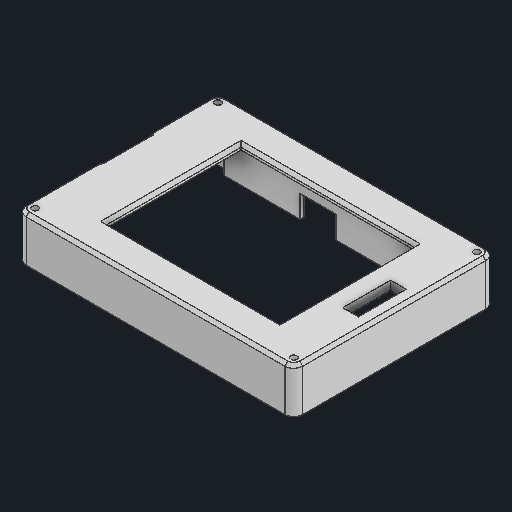
# Autodesk Inventor part: m1case
Saved by Autodesk Inventor 2027 (Build 310192000, 192)
## iProperties
Created: 2026-10-08
Part Number: m1case
Material: 일반
Document SubType Name: Modeling
Designer: khw
Density: 1 g/cm^3
Appearance: 기본값
Author: khw
Autodesk Inventor part; units mm, degrees
ref_plane "YZ Plane" through (0, 0, 0) normal (1, 0, 0) x (0, 1, 0)
ref_plane "XZ Plane" through (0, 0, 0) normal (0, 1, 0) x (-1, 0, 0)
ref_plane "XY Plane" through (0, 0, 0) normal (0, 0, 1) x (1, 0, 0)
sketch "스케치1" plane through (0, 0, 0) normal (0, 1, 0) x (-1, 0, 0)
  line L0 (-35, 25.5) -> (35, 25.5)
  line L1 (35, 25.5) -> (35, -25.5)
  line L2 (35, -25.5) -> (-35, -25.5)
  line L3 (-35, -25.5) -> (-35, 25.5)
  line L4 (-35, 25.5) -> (35, -25.5) construction
  line L5 (35, 25.5) -> (-35, -25.5) construction
  line L6 (-39.25, 21) -> (39.25, 21) construction
  line L7 (39.25, 21) -> (39.25, -21) construction
  line L8 (39.25, -21) -> (-39.25, -21) construction
  line L9 (-39.25, -21) -> (-39.25, 21) construction
  line L10 (-39.25, 21) -> (39.25, -21) construction
  line L11 (39.25, 21) -> (-39.25, -21) construction
  circle A0 centre (39.25, 21) radius 1.1
  circle A1 centre (39.25, -21) radius 1.1
  circle A2 centre (-39.25, -21) radius 1.1
  circle A3 centre (-39.25, 21) radius 1.1
  line L12 (-44.25, 27.5) -> (44.25, 27.5)
  line L13 (44.25, 27.5) -> (44.25, -27.5)
  line L14 (44.25, -27.5) -> (-44.25, -27.5)
  line L15 (-44.25, -27.5) -> (-44.25, 27.5)
  line L16 (-44.25, 27.5) -> (44.25, -27.5) construction
  line L17 (44.25, 27.5) -> (-44.25, -27.5) construction
  line L18 (-46.25, -29.5) -> (46.25, -29.5)
  line L19 (46.25, -29.5) -> (46.25, 29.5)
  line L20 (46.25, 29.5) -> (-46.25, 29.5)
  line L21 (-46.25, 29.5) -> (-46.25, -29.5)
  circle A4 centre (-39.25, 21) radius 3
  circle A5 centre (-39.25, -21) radius 3
  circle A6 centre (39.25, -21) radius 3
  circle A7 centre (39.25, 21) radius 3
  line L22 (-36.25, 21) -> (-36.25, 27.5)
  line L23 (-39.25, 18) -> (-44.25, 18)
  line L24 (-39.25, -18) -> (-44.25, -18)
  line L25 (-36.25, -21) -> (-36.25, -27.5)
  line L26 (39.25, -18) -> (44.25, -18)
  line L27 (36.25, -21) -> (36.25, -27.5)
  line L28 (39.25, 18) -> (44.25, 18)
  line L29 (36.25, 21) -> (36.25, 27.5)
  point P0 (0, 0)
  dimension "d0" = 70
  dimension "d1" = 51
  dimension "d2" = 78.5
  dimension "d3" = 42
  dimension "d4" = 2.2
  dimension "d5" = 2.2
  dimension "d6" = 2.2
  dimension "d7" = 2.2
  dimension "d8" = 2
  dimension "d9" = 5
  dimension "d10" = 2
  dimension "d16" = 6
  dimension "d17" = 6
  dimension "d18" = 6
  dimension "d19" = 6
  constraints: 60 end point, 18 point on line, 10 perpendicular, 8 centre point, 8 coincident, 8 parallel, 8 point on circle, 6 midpoint, 5 tangent, 3 horizontal, 3 other
  measures "d0" distance of L1.end L2.end
  measures "d1" distance of L0.end L1.end
  measures "d2" distance of L7.end L8.end
  measures "d3" distance of L6.end L7.end
  measures "d4" diameter of A0
  measures "d5" diameter of A1
  measures "d6" diameter of A2
  measures "d7" diameter of A3
  measures "d8" distance between parallel lines of L14 L2
  measures "d9" distance from line of L13 L7.end
  measures "d10" distance between parallel lines of L14 L18
  measures "d16" diameter of A5
  measures "d17" diameter of A4
  measures "d18" diameter of A6
  measures "d19" diameter of A7
extrude "돌출1" add sketch "스케치1" along normal blind 3 contours A0 | A1 | A2 | A3 | L12 L22 A4 L23 L15 | L12 L29 A7 L28 L13 L26 A6 L27 L14 L25 A5 L24 L15 L23 A4 L22 | L12 L13 L28 A7 L29 | A4 | L24 A5 L25 L14 L15 | A7 | A5 | L13 L14 L27 A6 L26 | A6 | L21 L20 L19 L18
extrude "돌출2" add sketch "스케치1" against normal blind 10 contours L21 L20 L19 L18
extrude "돌출3" add sketch "스케치1" against normal blind 3 contours L12 L22 A4 L23 L15 | L12 L13 L28 A7 L29 | A4 | L24 A5 L25 L14 L15 | A7 | A5 | L13 L14 L27 A6 L26 | A6
ref_plane "작업 평면1" through (0, 1.2, 0) normal (0, -1, 0) x (1, 0, 0)
sketch "스케치3" plane through (0, 1.2, 0) normal (0, -1, 0) x (1, 0, 0)
  line L0 (-39.25, 18) -> (-44.25, 18) projected
  line L1 (-44.25, 18) -> (-44.25, -18) projected
  line L2 (-44.25, -18) -> (-39.25, -18) projected
  arc A0 (-36.25, -21) -> (-39.25, -18) centre (-39.25, -21) ccw projected
  line L3 (-36.25, -21) -> (-36.25, -27.5) projected
  line L4 (-36.25, -27.5) -> (36.25, -27.5) projected
  line L5 (36.25, -27.5) -> (36.25, -21) projected
  arc A1 (39.25, -18) -> (36.25, -21) centre (39.25, -21) ccw projected
  line L6 (39.25, -18) -> (44.25, -18) projected
  line L7 (44.25, -18) -> (44.25, 18) projected
  line L8 (44.25, 18) -> (39.25, 18) projected
  arc A2 (36.25, 21) -> (39.25, 18) centre (39.25, 21) ccw projected
  line L9 (36.25, 21) -> (36.25, 27.5) projected
  line L10 (36.25, 27.5) -> (-36.25, 27.5) projected
  line L11 (-36.25, 27.5) -> (-36.25, 21) projected
  arc A3 (-39.25, 18) -> (-36.25, 21) centre (-39.25, 21) ccw projected
  line L12 (35, 25.5) -> (-35, 25.5) projected
  line L13 (35, -25.5) -> (35, 25.5) projected
  line L14 (-35, -25.5) -> (35, -25.5) projected
  line L15 (-35, 25.5) -> (-35, -25.5) projected
  line L16 (30.5, 22.5) -> (-27.5, 22.5)
  line L17 (-27.5, 22.5) -> (-27.5, -22.5)
  line L18 (-27.5, -22.5) -> (30.5, -22.5)
  line L19 (30.5, -22.5) -> (30.5, 22.5)
  line L20 (35, -25.5) -> (35, 25.5) projected
  point P0 (0, 0)
  point P1 (-27.5, 0)
  point P2 (30.5, 0)
  point P3 (35, 0)
  dimension "d23" = 58
  dimension "d24" = 45
  dimension "d25" = 7.5
  constraints: 8 end point, 3 midpoint, 2 parallel, 1 horizontal, 1 horizontal alignment, 1 perpendicular
  measures "d23" distance of L18.end L17.end
  measures "d24" distance of L17.end L16.end
  measures "d25" distance from line of L15 point (-27.5, 0)
extrude "돌출4" add sketch "스케치3" against normal up to surface (1.8 mm away) contours L13 L14 L15 L12
chamfer "모따기1" distance 1 angle 45 4 edges at (1.5, 3, -22.5) (-27.5, 3, 0) (1.5, 3, 22.5) (30.5, 3, 0)
ref_plane "작업 평면2" through (0, -4.5, 0) normal (0, -1, 0) x (1, 0, 0)
sketch "스케치4" plane through (0, -4.5, 0) normal (0, -1, 0) x (1, 0, 0)
  line L0 (-46.25, -6.5) -> (-44.25, -6.5)
  line L1 (-44.25, -6.5) -> (-44.25, 2.5)
  line L2 (-44.25, 2.5) -> (-46.25, 2.5)
  line L3 (-46.25, 2.5) -> (-46.25, -6.5)
  line L4 (-44.25, -27.5) -> (-44.25, 27.5) projected
  line L5 (-46.25, 29.5) -> (-46.25, -29.5) projected
  line L6 (-45.25, -10.5) -> (-46.25, -10.5)
  line L7 (-46.25, -10.5) -> (-46.25, 6.5)
  line L8 (-46.25, 6.5) -> (-45.25, 6.5)
  line L9 (-45.25, 6.5) -> (-45.25, -10.5)
  point P0 (0, 0)
  point P1 (-45.25, -6.5)
  point P2 (-45.25, 2.5)
  point P3 (-46.25, 6.5)
  point P4 (-46.25, -10.5)
  point P5 (-44.25, 0)
  point P6 (-44.25, -2)
  point P7 (-46.25, -2)
  dimension "d32" = 9
  dimension "d33" = 1
  dimension "d34" = 4
  dimension "d86" = 2
  constraints: 16 end point, 4 midpoint, 4 parallel, 2 horizontal, 2 perpendicular, 2 point on line
  measures "d32" distance of L1.end L0.end
  measures "d33" distance between parallel lines of L3 L9
  measures "d34" distance between parallel lines of L0 L6
  measures "d86" distance of point (-44.25, 0) point (-44.25, -2)
extrude "돌출5" cut sketch "스케치4" along normal blind 10
sketch "스케치5" plane through (0, 0, 0) normal (0, -1, 0) x (1, 0, 0)
  line L0 (37, 8) -> (42.25, 8)
  line L1 (42.25, 8) -> (42.25, -8)
  line L2 (42.25, -8) -> (37, -8)
  line L3 (37, -8) -> (37, 8)
  line L4 (44.25, 27.5) -> (44.25, -27.5) projected
  line L5 (35, -25.5) -> (35, 25.5) projected
  line L6 (37, 8) -> (42.25, 7.1992)
  line L7 (37, 5.9769) -> (39.9421, 5.5281)
  line L8 (39.9421, 5.5281) -> (38.5, 4)
  line L9 (38.5, 4) -> (42.25, 4) construction
  line L10 (42.25, 5.0596) -> (41.25, 4)
  line L11 (37, 0) -> (42.25, 0.8008)
  line L12 (37, 2.0231) -> (39.9421, 2.4719)
  line L13 (39.9421, 2.4719) -> (38.5, 4)
  line L14 (42.25, 2.9404) -> (41.25, 4)
  line L15 (42.25, -3) -> (41.75, -2.5)
  line L16 (41.75, -2.5) -> (40.75, -2.5)
  line L17 (40.75, -2.5) -> (40.75, -3)
  line L18 (40.75, -3) -> (37.5, -3)
  line L19 (37.5, -3) -> (37, -2.5)
  line L20 (37, -5.5) -> (37.5, -5)
  line L21 (37.5, -5) -> (42.25, -5)
  line L22 (37.5, -3) -> (37.5, -5) construction
  point P0 (0, 0)
  point P1 (42.25, 0)
  point P2 (44.25, 0)
  point P3 (39.221, 4.764)
  point P4 (39.221, 3.236)
  point P5 (39.875, -5)
  point P6 (37.5, -4)
  dimension "d37" = 2
  dimension "d38" = 2
  dimension "d39" = 16
  dimension "d40" = 2
  dimension "d41" = 2
  dimension "d42" = 2
  dimension "d43" = 1
  dimension "d44" = 0.5
  dimension "d45" = 4
  dimension "d46" = 0.5
  dimension "d47" = 45
  dimension "d48" = 1.5
  dimension "d49" = 1
  dimension "d50" = 1.5
  dimension "d51" = 8.673
  constraints: 42 end point, 10 point on line, 6 midpoint, 6 symmetric about line, 5 parallel, 5 perpendicular, 2 horizontal, 1 horizontal alignment, 1 vertical
  measures "d37" distance between parallel lines of L4 L1
  measures "d38" distance between parallel lines of L3 L5
  measures "d39" distance of L0.end L1.end
  measures "d40" distance between parallel lines of L7 L6
  measures "d41" distance from line of L10 point (39.221, 4.764)
  measures "d42" distance from line of point (39.875, -5) L18
  measures "d43" distance of L15.end L16.end
  measures "d44" distance of L16.end L17.end
  measures "d45" vertical distance of L11.start point (37.5, -4)
  measures "d46" distance between parallel lines of L3 L22
  measures "d47" angle of L17 L15
  measures "d48" distance of L15.start L17.end
  measures "d49" distance of L9.end L10.end
  measures "d50" distance from line of L3 L8.end
  measures "d51" angle of L0 L6
extrude "돌출6" cut sketch "스케치5" against normal blind 10
sketch "스케치7" plane through (0, -10, 0) normal (0, -1, 0) x (1, 0, 0)
  line L0 (-45.25, -10.5) -> (-46.25, -10.5) projected
  line L1 (-46.25, -10.5) -> (-46.25, -29.5) projected
  line L2 (-46.25, -29.5) -> (46.25, -29.5) projected
  line L3 (46.25, -29.5) -> (46.25, 29.5) projected
  line L4 (46.25, 29.5) -> (-46.25, 29.5) projected
  line L5 (-46.25, 29.5) -> (-46.25, 6.5) projected
  line L6 (-46.25, 6.5) -> (-45.25, 6.5) projected
  line L7 (-45.25, 6.5) -> (-45.25, 2.5) projected
  line L8 (-45.25, 2.5) -> (-44.25, 2.5) projected
  line L9 (-44.25, 2.5) -> (-44.25, 27.5) projected
  line L10 (-44.25, 27.5) -> (44.25, 27.5) projected
  line L11 (44.25, 27.5) -> (44.25, -27.5) projected
  line L12 (44.25, -27.5) -> (-44.25, -27.5) projected
  line L13 (-44.25, -27.5) -> (-44.25, -6.5) projected
  line L14 (-44.25, -6.5) -> (-45.25, -6.5) projected
  line L15 (-45.25, -6.5) -> (-45.25, -10.5) projected
  line L16 (-46.25, 33.6) -> (46.25, 33.6)
  line L17 (46.25, 33.6) -> (46.25, -33.6)
  line L18 (46.25, -33.6) -> (-46.25, -33.6)
  line L19 (-46.25, -33.6) -> (-46.25, 33.6)
  line L20 (-46.25, -10.5) -> (-46.25, 6.5) projected
  line L21 (43.25, 30.6) -> (-43.25, 30.6) construction
  line L22 (-43.25, 30.6) -> (-43.25, -30.6) construction
  line L23 (-43.25, -30.6) -> (43.25, -30.6) construction
  line L24 (43.25, -30.6) -> (43.25, 30.6) construction
  circle A0 centre (-43.25, 30.6) radius 1.1
  circle A1 centre (43.25, 30.6) radius 1.1
  circle A2 centre (-43.25, -30.6) radius 1.1
  circle A3 centre (43.25, -30.6) radius 1.1
  line L25 (-46.25, -29.5) -> (46.25, -29.5) projected
  point P0 (0, 0)
  point P1 (46.25, 0)
  point P2 (-46.25, 0)
  point P3 (43.25, -29.5)
  point P4 (-43.25, -29.5)
  point P5 (-43.25, 29.5)
  point P6 (43.25, 29.5)
  dimension "d61" = 3
  dimension "d62" = 2.2
  dimension "d63" = 2.2
  dimension "d64" = 2.2
  dimension "d65" = 2.2
  constraints: 16 end point, 4 centre point, 4 coincident, 4 parallel, 3 midpoint, 2 perpendicular, 1 horizontal, 1 point on line, 1 tangent, 3 other
  measures "d61" distance between parallel lines of L16 L21
  measures "d62" diameter of A0
  measures "d63" diameter of A1
  measures "d64" diameter of A2
  measures "d65" diameter of A3
extrude "돌출8" add sketch "스케치7" against normal up to surface (13 mm away) contours L2 L17 L18 L19 | L19 L16 L17 L4
sketch "스케치6" plane through (0, -4.5, 0) normal (0, -1, 0) x (1, 0, 0)
  line L0 (-10.75, -29.5) -> (1.25, -29.5)
  line L1 (1.25, -29.5) -> (1.25, -27.5)
  line L2 (1.25, -27.5) -> (-10.75, -27.5)
  line L3 (-10.75, -27.5) -> (-10.75, -29.5)
  arc A0 (-36.25, -21) -> (-39.25, -18) centre (-39.25, -21) ccw projected
  line L4 (-39.25, -18) -> (-44.25, -18) projected
  line L5 (-44.25, -27.5) -> (-44.25, -18) projected
  line L6 (-36.25, -27.5) -> (-44.25, -27.5) projected
  line L7 (-36.25, -27.5) -> (-36.25, -21) projected
  circle A1 centre (-39.25, -21) radius 1.1 projected
  line L8 (44.25, -27.5) -> (-44.25, -27.5) projected
  line L9 (-46.25, -29.5) -> (46.25, -29.5) projected
  line L10 (1.25, -29.5) -> (5.35, -33.6)
  line L11 (-46.25, -33.6) -> (46.25, -33.6) projected
  line L12 (-10.75, -29.5) -> (-14.85, -33.6)
  point P0 (0, 0)
  point P1 (-4.75, -27.5)
  point P2 (-4.75, -29.5)
  dimension "d54" = 28.5
  dimension "d55" = 12
  dimension "d68" = 45
  dimension "d69" = 45
  constraints: 12 end point, 4 point on line, 2 midpoint, 2 parallel, 1 horizontal, 1 perpendicular
  measures "d54" distance from line of L3 A0.centre
  measures "d55" distance of L1.end L2.end
  measures "d68" angle of L9 L10
  measures "d69" angle of L9 L12
extrude "돌출7" cut sketch "스케치6" along normal blind 2 contours L3 L2 L1 L0 | L0 L10 L11 L12
fillet "모깎기1" radius 3 4 edges at (46.25, -3.5, 33.6) (46.25, -3.5, -33.6) (-46.25, -3.5, -33.6) (-46.25, -3.5, 33.6)
sketch "스케치8" plane through (0, 0, 0) normal (0, -1, 0) x (1, 0, 0)
  line L0 (37, 8) -> (42.25, 8) projected
  line L1 (42.25, 8) -> (42.25, -8) projected
  line L2 (42.25, -8) -> (37, -8) projected
  line L3 (37, -8) -> (37, 8) projected
  line L4 (-39.25, 18) -> (-44.25, 18) projected
  line L5 (-44.25, 18) -> (-44.25, -18) projected
  line L6 (-44.25, -18) -> (-39.25, -18) projected
  arc A0 (-36.25, -21) -> (-39.25, -18) centre (-39.25, -21) ccw projected
  line L7 (-36.25, -21) -> (-36.25, -27.5) projected
  line L8 (-36.25, -27.5) -> (36.25, -27.5) projected
  line L9 (36.25, -27.5) -> (36.25, -21) projected
  arc A1 (39.25, -18) -> (36.25, -21) centre (39.25, -21) ccw projected
  line L10 (39.25, -18) -> (44.25, -18) projected
  line L11 (44.25, -18) -> (44.25, 18) projected
  line L12 (44.25, 18) -> (39.25, 18) projected
  arc A2 (36.25, 21) -> (39.25, 18) centre (39.25, 21) ccw projected
  line L13 (36.25, 21) -> (36.25, 27.5) projected
  line L14 (36.25, 27.5) -> (-36.25, 27.5) projected
  line L15 (-36.25, 27.5) -> (-36.25, 21) projected
  arc A3 (-39.25, 18) -> (-36.25, 21) centre (-39.25, 21) ccw projected
  line L16 (35, 25.5) -> (-35, 25.5) projected
  line L17 (35, -25.5) -> (35, 25.5) projected
  line L18 (-35, -25.5) -> (35, -25.5) projected
  line L19 (-35, 25.5) -> (-35, -25.5) projected
  line L20 (36.25, -25.5) -> (-36.25, -25.5)
  line L21 (-10.75, -27.5) -> (1.25, -27.5) projected
  line L22 (1.25, -27.5) -> (1.25, -25.5)
  line L23 (-10.75, -25.5) -> (-10.75, -27.5)
  point P0 (0, 0)
  dimension "d74" = 2
  constraints: 6 end point, 4 point on line, 3 perpendicular
  measures "d74" distance between parallel lines of L8 L20
extrude "돌출9" add sketch "스케치8" along normal up to surface (10 mm away) contours L20 L18 L23 L8 L7 | L22 L18 L20 L9 L8
extrude "돌출10" add sketch "스케치8" along normal up to surface (4.5 mm away) contours L23 L18 L22 L8
sketch "스케치9" plane through (0, -4.5, 0) normal (0, -1, 0) x (1, 0, 0)
  line L0 (5.35, -33.6) -> (3.35, -31.6) projected
  line L1 (3.35, -31.6) -> (-12.85, -31.6) projected
  line L2 (-12.85, -31.6) -> (-14.85, -33.6) projected
  line L3 (-14.85, -33.6) -> (5.35, -33.6) projected
  line L4 (5.35, -33.6) -> (1.25, -29.5) projected
  line L5 (1.25, -29.5) -> (1.25, -25.5) projected
  line L6 (-10.75, -25.5) -> (1.25, -25.5) projected
  line L7 (-10.75, -29.5) -> (-10.75, -25.5) projected
  line L8 (-10.75, -29.5) -> (-14.85, -33.6) projected
  line L9 (-4.75, -25.5) -> (-4.75, -26.5)
  arc A0 (21.25, -33.6) -> (-4.75, -26.5) centre (-4.75, -77.6556) ccw
  line L10 (-4.75, -26.5) -> (-4.75, -33.6)
  arc A1 (-4.75, -26.5) -> (-30.75, -33.6) centre (-4.75, -77.6556) ccw
  line L11 (-43.25, -33.6) -> (43.25, -33.6) projected
  line L12 (5.35, -33.6) -> (-14.85, -33.6) projected
  point P0 (0, 0)
  point P1 (1.25, -27.5)
  point P2 (-30.75, -33.6)
  dimension "d79" = 1
  dimension "d80" = 20
  constraints: 4 end point, 4 point on circle, 3 midpoint, 2 centre point, 2 symmetric about line, 1 concentric, 1 point on line, 1 vertical, 1 other
  measures "d79" distance of L9.start L9.end
  measures "d80" horizontal distance of A0.start point (1.25, -27.5)
extrude "돌출11" cut sketch "스케치9" along normal through all contours L3 L10 L1 L0 | L0 L4 L5 A0 L11 | L1 L10 A0 L5 L4 | L3 L2 L1 L10 | L1 L8 L7 A1 L10 | L11 A1 L7 L8 L2
chamfer "모따기4" distance 6.74 angle 45 1 edges at (-4.75, -4.5, -33.6)
chamfer "모따기5" distance 1 angle 45 3 edges at (-46.25, -4.5, -2) (-45.25, -7.25, -10.5) (-45.25, -7.25, 6.5)
sketch "스케치10" plane through (0, -10, 0) normal (0, -1, 0) x (1, 0, 0)
  circle A0 centre (43.25, 30.6) radius 1.1 projected
  circle A1 centre (-43.25, 30.6) radius 1.1 projected
  circle A2 centre (43.25, -30.6) radius 1.1 projected
  arc A3 (21.25, -33.6) -> (1.25, -26.8531) centre (-4.75, -77.6556) ccw projected
  line L0 (21.25, -33.6) -> (43.25, -33.6) projected
  arc A4 (43.25, -33.6) -> (46.25, -30.6) centre (43.25, -30.6) ccw projected
  line L1 (46.25, -30.6) -> (46.25, 30.6) projected
  arc A5 (46.25, 30.6) -> (43.25, 33.6) centre (43.25, 30.6) ccw projected
  line L2 (43.25, 33.6) -> (-43.25, 33.6) projected
  arc A6 (-43.25, 33.6) -> (-46.25, 30.6) centre (-43.25, 30.6) ccw projected
  line L3 (-46.25, 30.6) -> (-46.25, 6.5) projected
  line L4 (-45.25, 5.5) -> (-46.25, 6.5) projected
  line L5 (-45.25, 5.5) -> (-45.25, 2.5) projected
  line L6 (-45.25, 2.5) -> (-44.25, 2.5) projected
  line L7 (-44.25, 2.5) -> (-44.25, 27.5) projected
  line L8 (-44.25, 27.5) -> (44.25, 27.5) projected
  line L9 (44.25, 27.5) -> (44.25, -27.5) projected
  line L10 (44.25, -27.5) -> (36.25, -27.5) projected
  line L11 (36.25, -25.5) -> (36.25, -27.5) projected
  line L12 (1.25, -25.5) -> (36.25, -25.5) projected
  line L13 (1.25, -26.8531) -> (1.25, -25.5) projected
  circle A7 centre (-43.25, -30.6) radius 1.1 projected
  arc A8 (-10.75, -26.8531) -> (-30.75, -33.6) centre (-4.75, -77.6556) ccw projected
  line L14 (-10.75, -25.5) -> (-10.75, -26.8531) projected
  line L15 (-36.25, -25.5) -> (-10.75, -25.5) projected
  line L16 (-36.25, -27.5) -> (-36.25, -25.5) projected
  line L17 (-36.25, -27.5) -> (-44.25, -27.5) projected
  line L18 (-44.25, -27.5) -> (-44.25, -6.5) projected
  line L19 (-44.25, -6.5) -> (-45.25, -6.5) projected
  line L20 (-45.25, -6.5) -> (-45.25, -9.5) projected
  line L21 (-46.25, -10.5) -> (-45.25, -9.5) projected
  line L22 (-46.25, -10.5) -> (-46.25, -30.6) projected
  arc A9 (-46.25, -30.6) -> (-43.25, -33.6) centre (-43.25, -30.6) ccw projected
  line L23 (-43.25, -33.6) -> (-30.75, -33.6) projected
  line L24 (1.3083, -26.86) -> (-10.8083, -26.86) projected
  arc A10 (1.3083, -26.86) -> (1.25, -26.8531) centre (-4.75, -77.6556) ccw projected
  line L25 (1.25, -26.8531) -> (1.25, -25.5) projected
  line L26 (-10.75, -25.5) -> (1.25, -25.5) projected
  line L27 (-10.75, -26.8531) -> (-10.75, -25.5) projected
  arc A11 (-10.75, -26.8531) -> (-10.8083, -26.86) centre (-4.75, -77.6556) ccw projected
  line L28 (-46.25, 6.5) -> (-46.25, -10.5)
  point P0 (0, 0)
  constraints: 2 end point, 1 vertical
extrude "돌출12" add sketch "스케치10" along normal blind 2 separate body
extrude "돌출13" add sketch "스케치10" against normal blind 3 contours L24 A8 L14 L26 L13 A3 bodies 2
sketch "스케치11" plane through (0, -7, 0) normal (0, 1, 0) x (1, 0, 0)
  line L0 (-10.75, 26.8531) -> (-10.75, 25.5) projected
  line L1 (-10.75, 25.5) -> (1.25, 25.5) projected
  line L2 (1.25, 25.5) -> (1.25, 26.8531) projected
  arc A0 (1.25, 26.8531) -> (1.3083, 26.86) centre (-4.75, 77.6556) ccw projected
  line L3 (1.3083, 26.86) -> (-10.8083, 26.86) projected
  arc A1 (-10.8083, 26.86) -> (-10.75, 26.8531) centre (-4.75, 77.6556) ccw projected
  line L4 (-10.55, 25.5) -> (-10.55, 26.86)
  line L5 (1.05, 25.5) -> (1.05, 26.86)
  point P0 (0, 0)
  dimension "d94" = 0.2
  dimension "d95" = 0.2
  constraints: 4 end point, 4 point on line, 1 perpendicular, 1 vertical
  measures "d94" distance between parallel lines of L2 L5
  measures "d95" distance between parallel lines of L4 L0
extrude "돌출14" cut sketch "스케치11" against normal up to surface (3 mm away) contours A1 L3 L4 L1 L0 | L5 L3 A0 L2 L1 bodies 2
sketch "스케치12" plane through (0, -10, 0) normal (0, 1, 0) x (1, 0, 0)
  line L0 (-45.25, 6.5) -> (-45.25, -2.5) projected
  line L1 (-45.25, 6.5) -> (-44.25, 6.5) projected
  line L2 (-44.25, -2.5) -> (-44.25, 6.5) projected
  line L3 (-44.25, -2.5) -> (-45.25, -2.5) projected
  line L4 (-45.25, 6.3) -> (-44.25, 6.3)
  line L5 (-45.25, -2.3) -> (-44.25, -2.3)
  point P0 (0, 0)
  point P1 (-44.75, -2.5)
  dimension "d98" = 0.2
  dimension "d99" = 0.2
  constraints: 4 end point, 4 point on line, 1 horizontal, 1 midpoint, 1 perpendicular
  measures "d98" distance from line of point (-44.75, -2.5) L5
  measures "d99" distance between parallel lines of L1 L4
extrude "돌출15" add sketch "스케치12" along normal blind 1.8 contours L4 L2 L5 L0 bodies 2
fillet "모깎기2" radius 2 2 edges at (-44.25, -10, -2) (-4.75, -10, -25.5)
sketch "스케치13" plane through (0, 0, 0) normal (0, -1, 0) x (1, 0, 0)
  line L0 (-44.25, 27.5) -> (44.25, 27.5)
  line L1 (37, 8) -> (42.25, 8)
  line L2 (42.25, 8) -> (42.25, -8)
  line L3 (42.25, -8) -> (37, -8)
  line L4 (37, -8) -> (37, 8)
  line L5 (-36.25, -25.5) -> (-35, -25.5)
  line L6 (-35, 25.5) -> (-35, -25.5)
  line L7 (35, 25.5) -> (-35, 25.5)
  line L8 (35, -25.5) -> (35, 25.5)
  line L9 (35, -25.5) -> (36.25, -25.5)
  line L10 (36.25, -25.5) -> (36.25, -21)
  arc A0 (39.25, -18) -> (36.25, -21) centre (39.25, -21) ccw
  line L11 (39.25, -18) -> (44.25, -18)
  line L12 (44.25, -18) -> (44.25, 18)
  line L13 (44.25, 18) -> (39.25, 18)
  arc A1 (36.25, 21) -> (39.25, 18) centre (39.25, 21) ccw
  line L14 (36.25, 21) -> (36.25, 27.5)
  line L15 (36.25, 27.5) -> (-36.25, 27.5)
  line L16 (-36.25, 27.5) -> (-36.25, 21)
  arc A2 (-39.25, 18) -> (-36.25, 21) centre (-39.25, 21) ccw
  line L17 (-39.25, 18) -> (-44.25, 18)
  line L18 (-44.25, 18) -> (-44.25, -18)
  line L19 (-44.25, -18) -> (-39.25, -18)
  arc A3 (-36.25, -21) -> (-39.25, -18) centre (-39.25, -21) ccw
  line L20 (-36.25, -21) -> (-36.25, -25.5)
  line L21 (-36.25, -27.5) -> (-44.25, -27.5)
  line L22 (-43.25, 27.5) -> (-43.25, -27.5)
  arc A4 (-39.25, 18) -> (-36.25, 21) centre (-39.25, 21) ccw
  line L23 (-36.25, 21) -> (-36.25, 27.5)
  line L24 (-44.25, 27.5) -> (-36.25, 27.5)
  line L25 (-44.25, 18) -> (-44.25, 27.5)
  line L26 (-44.25, 18) -> (-39.25, 18)
  circle A5 centre (-39.25, 21) radius 1.1
  arc A6 (-36.25, -21) -> (-39.25, -18) centre (-39.25, -21) ccw
  line L27 (-39.25, -18) -> (-44.25, -18)
  line L28 (-44.25, -27.5) -> (-44.25, -18)
  line L29 (-36.25, -27.5) -> (-44.25, -27.5)
  line L30 (-36.25, -27.5) -> (-36.25, -25.5)
  line L31 (-36.25, -25.5) -> (-36.25, -21)
  circle A7 centre (-39.25, -21) radius 1.1
  line L32 (-45.25, 5.5) -> (-46.25, 6.5)
  line L33 (-46.25, 6.5) -> (-46.25, -10.5)
  line L34 (-46.25, -10.5) -> (-45.25, -9.5)
  line L35 (-45.25, -9.5) -> (-45.25, -6.5)
  line L36 (-45.25, -6.5) -> (-45.25, 2.5)
  line L37 (-45.25, 2.5) -> (-45.25, 5.5)
  line L38 (-44.25, 2.5) -> (-44.25, 27.5)
  circle A8 centre (43.25, 30.6) radius 1.1
  circle A9 centre (-43.25, 30.6) radius 1.1
  circle A10 centre (43.25, -30.6) radius 1.1
  arc A11 (21.25, -33.6) -> (1.25, -26.8531) centre (-4.75, -77.6556) ccw
  line L39 (21.25, -33.6) -> (43.25, -33.6)
  arc A12 (43.25, -33.6) -> (46.25, -30.6) centre (43.25, -30.6) ccw
  line L40 (46.25, -30.6) -> (46.25, 30.6)
  arc A13 (46.25, 30.6) -> (43.25, 33.6) centre (43.25, 30.6) ccw
  line L41 (43.25, 33.6) -> (-43.25, 33.6)
  arc A14 (-43.25, 33.6) -> (-46.25, 30.6) centre (-43.25, 30.6) ccw
  line L42 (-46.25, 30.6) -> (-46.25, 6.5)
  line L43 (-45.25, 5.5) -> (-46.25, 6.5)
  line L44 (-45.25, 5.5) -> (-45.25, 2.5)
  line L45 (-45.25, 2.5) -> (-44.25, 2.5)
  line L46 (-44.25, 2.5) -> (-44.25, 27.5)
  line L47 (-44.25, 27.5) -> (44.25, 27.5)
  line L48 (44.25, 27.5) -> (44.25, -27.5)
  line L49 (44.25, -27.5) -> (36.25, -27.5)
  line L50 (36.25, -25.5) -> (36.25, -27.5)
  line L51 (1.25, -25.5) -> (36.25, -25.5)
  line L52 (1.25, -26.8531) -> (1.25, -25.5)
  line L53 (-45.25, -6.5) -> (-45.25, 2.5)
  line L54 (-45.25, -6.5) -> (-44.25, -6.5)
  line L55 (-44.25, 2.5) -> (-44.25, -6.5)
  line L56 (-44.25, 2.5) -> (-45.25, 2.5)
  circle A15 centre (-43.25, -30.6) radius 1.1
  arc A16 (-10.75, -26.8531) -> (-30.75, -33.6) centre (-4.75, -77.6556) ccw
  line L57 (-10.75, -25.5) -> (-10.75, -26.8531)
  line L58 (-36.25, -25.5) -> (-10.75, -25.5)
  line L59 (-36.25, -27.5) -> (-36.25, -25.5)
  line L60 (-36.25, -27.5) -> (-44.25, -27.5)
  line L61 (-44.25, -27.5) -> (-44.25, -6.5)
  line L62 (-44.25, -6.5) -> (-45.25, -6.5)
  line L63 (-45.25, -6.5) -> (-45.25, -9.5)
  line L64 (-46.25, -10.5) -> (-45.25, -9.5)
  line L65 (-46.25, -10.5) -> (-46.25, -30.6)
  arc A17 (-46.25, -30.6) -> (-43.25, -33.6) centre (-43.25, -30.6) ccw
  line L66 (-43.25, -33.6) -> (-30.75, -33.6)
  point P0 (0, 0)
extrude "돌출16" add sketch "스케치13" along normal up to surface (10 mm away) contours L0 L22 L17 L25 | L17 L22 L19 L18 | L18 L54 L36 L45 | L22 L21 L28 L19 | L36 L35 L34 L33 L32 L37 bodies 1
sketch "스케치14" plane through (0, 0, 0) normal (0, -1, 0) x (1, 0, 0)
  line L0 (-43.25, -7.25) -> (-46.25, -7.25)
  line L1 (-46.25, -7.25) -> (-46.25, 3.25)
  line L2 (-46.25, 3.25) -> (-43.25, 3.25)
  line L3 (-43.25, 3.25) -> (-43.25, -7.25)
  circle A0 centre (-39.25, -21) radius 1.1 projected
  line L4 (-43.25, 27.5) -> (-43.25, -27.5) projected
  line L5 (-46.25, 30.6) -> (-46.25, -30.6) projected
  point P0 (0, 0)
  point P1 (-43.25, -2)
  point P2 (-46.25, 0)
  dimension "d106" = 19
  dimension "d107" = 10.5
  constraints: 8 end point, 2 midpoint, 2 parallel, 2 point on line, 1 horizontal, 1 perpendicular
  measures "d106" vertical distance of A0.centre point (-43.25, -2)
  measures "d107" distance of L0.end L1.end
extrude "돌출17" cut sketch "스케치14" along normal through all contours L0 L1 L2 L3 bodies 1
sketch "스케치15" plane through (0, 0, 0) normal (0, -1, 0) x (1, 0, 0)
  line L0 (-43.25, 18) -> (-43.25, 3.25) projected
  line L1 (-43.25, 3.25) -> (-46.25, 3.25) projected
  line L2 (-46.25, -7.25) -> (-46.25, 3.25) projected
  line L3 (-46.25, -7.25) -> (-43.25, -7.25) projected
  line L4 (-43.25, -7.25) -> (-43.25, -18) projected
  line L5 (-43.25, -18) -> (-39.25, -18) projected
  arc A0 (-36.25, -21) -> (-39.25, -18) centre (-39.25, -21) ccw projected
  line L6 (-36.25, -21) -> (-36.25, -25.5) projected
  line L7 (-36.25, -25.5) -> (-35, -25.5) projected
  line L8 (-35, 25.5) -> (-35, -25.5) projected
  line L9 (35, 25.5) -> (-35, 25.5) projected
  line L10 (35, -25.5) -> (35, 25.5) projected
  line L11 (35, -25.5) -> (36.25, -25.5) projected
  line L12 (36.25, -25.5) -> (36.25, -21) projected
  arc A1 (39.25, -18) -> (36.25, -21) centre (39.25, -21) ccw projected
  line L13 (39.25, -18) -> (44.25, -18) projected
  line L14 (44.25, -18) -> (44.25, 18) projected
  line L15 (44.25, 18) -> (39.25, 18) projected
  arc A2 (36.25, 21) -> (39.25, 18) centre (39.25, 21) ccw projected
  line L16 (36.25, 21) -> (36.25, 27.5) projected
  line L17 (36.25, 27.5) -> (-36.25, 27.5) projected
  line L18 (-36.25, 27.5) -> (-36.25, 21) projected
  arc A3 (-39.25, 18) -> (-36.25, 21) centre (-39.25, 21) ccw projected
  line L19 (-39.25, 18) -> (-43.25, 18) projected
  line L20 (37, 8) -> (42.25, 8) projected
  line L21 (42.25, 8) -> (42.25, -8) projected
  line L22 (42.25, -8) -> (37, -8) projected
  line L23 (37, -8) -> (37, 8) projected
  line L24 (-41.25, 18) -> (-41.25, -18)
  line L25 (-43.25, -7.25) -> (-43.25, -27.5) projected
  line L26 (-43.25, 18) -> (-43.25, 3.25) projected
  line L27 (-43.25, 3.25) -> (-43.25, -7.25)
  point P0 (0, 0)
  dimension "d113" = 2
  constraints: 4 end point, 2 midpoint, 1 parallel, 1 perpendicular, 1 vertical
  measures "d113" distance between parallel lines of L4 L24
extrude "돌출18" add sketch "스케치15" along normal blind 4.5 contours L27 L3 L2 L1 bodies 1
sketch "스케치16" plane through (0, -4.5, 0) normal (0, -1, 0) x (1, 0, 0)
  line L0 (-43.25, -7.25) -> (-43.25, 3.25) projected
  line L1 (-46.25, 3.25) -> (-43.25, 3.25) projected
  line L2 (-46.25, 3.25) -> (-46.25, -7.25) projected
  line L3 (-43.25, -7.25) -> (-46.25, -7.25) projected
  line L4 (-46.25, -2) -> (-35, -2) construction
  line L5 (-44.75, -7.25) -> (-44.75, -10.25)
  line L6 (-44.75, -10.25) -> (-46.25, -12.8481)
  line L7 (-46.25, -7.25) -> (-46.25, -30.6) projected
  line L8 (-44.75, 3.25) -> (-44.75, 6.25)
  line L9 (-44.75, 6.25) -> (-46.25, 8.8481)
  line L10 (-46.25, 30.6) -> (-46.25, -30.6) projected
  point P0 (0, 0)
  dimension "d116" = 3
  dimension "d117" = 150
  constraints: 10 end point, 3 symmetric about line, 2 midpoint, 1 point on line, 1 vertical
  measures "d116" distance of L5.start L5.end
  measures "d117" angle of L5 L6
extrude "돌출19" cut sketch "스케치16" along normal through all contours L5 L6 L7 L3 | L1 L10 L9 L8 bodies 1
fillet "모깎기3" radius 2 5 edges at (-43.25, -1.5, 18) (36.25, -1.5, 27.5) (44.25, -1.5, 18) (44.25, -1.5, -18) (-43.25, -1.5, -18)
sketch "스케치17" plane through (0, -4.5, 0) normal (0, -1, 0) x (1, 0, 0)
  line L0 (-46.25, -12.8481) -> (-46.25, 8.8481) projected
  line L1 (-46.25, -12.8481) -> (-44.75, -10.25) projected
  line L2 (-44.75, -10.25) -> (-44.75, -7.25) projected
  line L3 (-43.25, -7.25) -> (-44.75, -7.25) projected
  line L4 (-43.25, -7.25) -> (-43.25, 3.25) projected
  line L5 (-44.75, 3.25) -> (-43.25, 3.25) projected
  line L6 (-44.75, 3.25) -> (-44.75, 6.25) projected
  line L7 (-44.75, 6.25) -> (-46.25, 8.8481) projected
  line L8 (-44.75, 3.25) -> (-44.75, -7.25)
  point P0 (0, 0)
  constraints: 2 end point, 1 vertical
extrude "돌출20" cut sketch "스케치17" against normal blind 10 contours L0 L7 L6 L8 L2 L1 bodies 1
sketch "스케치18" plane through (0, -10, 0) normal (0, -1, 0) x (1, 0, 0)
  circle A0 centre (43.25, 30.6) radius 1.1 projected
  circle A1 centre (-43.25, 30.6) radius 1.1 projected
  circle A2 centre (43.25, -30.6) radius 1.1 projected
  line L0 (-46.25, 8.8481) -> (-44.75, 6.25) projected
  line L1 (-44.75, 6.25) -> (-44.75, 3.25) projected
  line L2 (-44.75, 3.25) -> (-43.25, 3.25) projected
  line L3 (-43.25, 27.5) -> (-43.25, 3.25) projected
  line L4 (-43.25, 27.5) -> (44.25, 27.5) projected
  line L5 (44.25, 27.5) -> (44.25, -27.5) projected
  line L6 (44.25, -27.5) -> (36.25, -27.5) projected
  line L7 (36.25, -25.5) -> (36.25, -27.5) projected
  line L8 (1.25, -25.5) -> (36.25, -25.5) projected
  line L9 (1.25, -26.8531) -> (1.25, -25.5) projected
  arc A3 (21.25, -33.6) -> (1.25, -26.8531) centre (-4.75, -77.6556) ccw projected
  line L10 (21.25, -33.6) -> (43.25, -33.6) projected
  arc A4 (43.25, -33.6) -> (46.25, -30.6) centre (43.25, -30.6) ccw projected
  line L11 (46.25, -30.6) -> (46.25, 30.6) projected
  arc A5 (46.25, 30.6) -> (43.25, 33.6) centre (43.25, 30.6) ccw projected
  line L12 (43.25, 33.6) -> (-43.25, 33.6) projected
  arc A6 (-43.25, 33.6) -> (-46.25, 30.6) centre (-43.25, 30.6) ccw projected
  line L13 (-46.25, 30.6) -> (-46.25, 8.8481) projected
  line L14 (-44.75, -7.25) -> (-44.75, -10.25) projected
  line L15 (-44.75, -10.25) -> (-46.25, -12.8481) projected
  line L16 (-46.25, -12.8481) -> (-46.25, -30.6) projected
  arc A7 (-46.25, -30.6) -> (-43.25, -33.6) centre (-43.25, -30.6) ccw projected
  line L17 (-43.25, -33.6) -> (-30.75, -33.6) projected
  arc A8 (-10.75, -26.8531) -> (-30.75, -33.6) centre (-4.75, -77.6556) ccw projected
  line L18 (-10.75, -25.5) -> (-10.75, -26.8531) projected
  line L19 (-36.25, -25.5) -> (-10.75, -25.5) projected
  line L20 (-36.25, -27.5) -> (-36.25, -25.5) projected
  line L21 (-36.25, -27.5) -> (-43.25, -27.5) projected
  line L22 (-43.25, -7.25) -> (-43.25, -27.5) projected
  line L23 (-43.25, -7.25) -> (-44.75, -7.25) projected
  circle A9 centre (-43.25, -30.6) radius 1.1 projected
  point P0 (0, 0)
extrude "돌출21" add sketch "스케치18" along normal blind 2 bodies 1
chamfer "모따기7" distance 1 angle 45 9 edges at (0, 3, -33.6) (45.3713, 3, -32.7213) (46.25, 3, 0) (45.3713, 3, 32.7213) (0, 3, 33.6) (-45.3713, 3, 32.7213) (-46.25, 3, 19.724) (-45.3713, 3, -32.7213) (-46.25, 3, -21.724)
equation "\"d5\" = d4"
equation "\"d6\" = d4"
equation "\"d7\" = d4"
equation "\"d63\" = d62"
equation "\"d64\" = d62"
equation "\"d65\" = d62"
